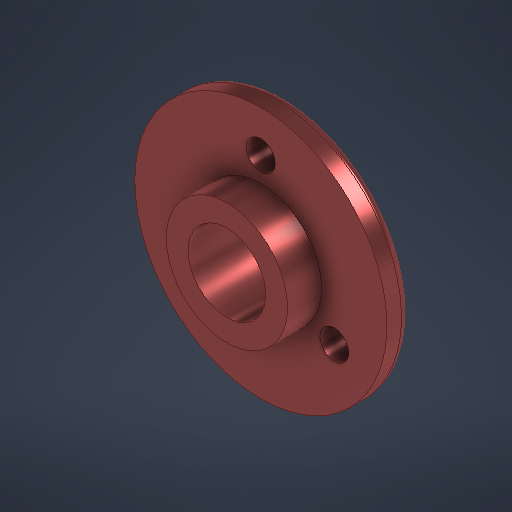
# Autodesk Inventor part: 4. End Bush
Saved by Autodesk Inventor 2025.2 (Build 292293000, 293)
## iProperties
Created: 2025-05-09
Part Number: 4. End Bush
Material: Steel, Mild
Document SubType Name: Modeling
Designer: trysm
Density: 7.85 g/cm^3
Appearance: Semi-Polished
Author: trysm
Autodesk Inventor part; units mm, degrees
ref_plane "YZ Plane" through (0, 0, 0) normal (1, 0, 0) x (0, 1, 0)
ref_plane "XZ Plane" through (0, 0, 0) normal (0, 1, 0) x (-1, 0, 0)
ref_plane "XY Plane" through (0, 0, 0) normal (0, 0, 1) x (1, 0, 0)
sketch "Sketch1" plane through (0, 0, 0) normal (0, 1, 0) x (-1, 0, 0)
  circle A0 centre (0, 0) radius 26
  circle A1 centre (0, 0) radius 12.5
  circle A2 centre (0, 0) radius 8
  circle A3 centre (0, 17.5) radius 3
  circle A4 centre (-15.1554, -8.75) radius 3
  circle A5 centre (15.1554, -8.75) radius 3
  dimension "d0" = 52
  dimension "d1" = 25
  dimension "d2" = 16
  dimension "d3" = 17.5
  dimension "d4" = 6
  dimension "d7" = 360
  constraints: 6 centre point, 3 coincident, 1 vertical alignment, 7 other
  measures "d0" diameter of A0
  measures "d1" diameter of A1
  measures "d2" diameter of A2
  measures "d3" distance of point (0, 0) A3.centre
  measures "d4" diameter of A3
extrude "Extrusion1" add sketch "Sketch1" against normal blind 5 contours A0
extrude "Extrusion2" add sketch "Sketch1" against normal blind 12 contours A1
fillet "Fillet1" radius 2 1 edges at (26, 0, 0)
body "Solid1"
